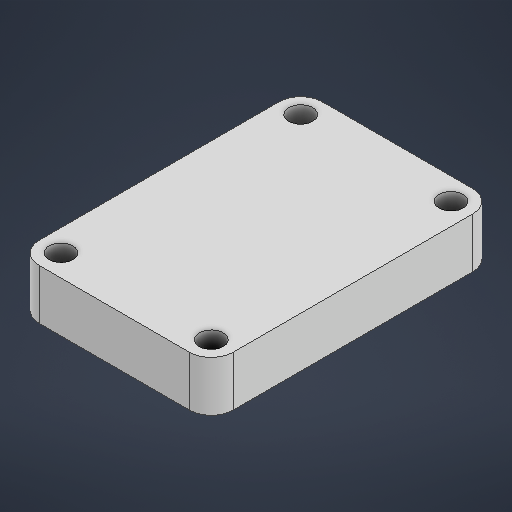
# Autodesk Inventor part: IMU
Saved by Autodesk Inventor 2026.2 (Build 302298010, 298A)
## iProperties
Created: 2026-07-16
Part Number: IMU
Material: Generic
Document SubType Name: Modeling
Designer: User
Density: 1 g/cm^3
Appearance: Default
Author: User
Autodesk Inventor part; units mm, degrees
ref_plane "YZ Plane" through (0, 0, 0) normal (1, 0, 0) x (0, 1, 0)
ref_plane "XZ Plane" through (0, 0, 0) normal (0, 1, 0) x (-1, 0, 0)
ref_plane "XY Plane" through (0, 0, 0) normal (0, 0, 1) x (1, 0, 0)
sketch "Sketch1" plane through (0, 0, 0) normal (0, 1, 0) x (-1, 0, 0)
  line L0 (0, 0) -> (17.8, 0)
  line L1 (17.8, 0) -> (17.8, -26)
  line L2 (17.8, -26) -> (0, -26)
  line L3 (0, -26) -> (0, 0)
  dimension "d0" = 17.8
  dimension "d1" = 26
  constraints: 8 end point, 2 parallel, 1 horizontal, 1 perpendicular
  measures "d0" distance of L1.end L2.end
  measures "d1" distance of L0.end L1.end
extrude "Extrusion1" add sketch "Sketch1" along normal blind 4.6
sketch "Sketch2" plane through (0, 4.6, 0) normal (0, 1, 0) x (1, 0, 0)
  line L0 (0, 0) -> (0, 26) projected
  line L1 (-17.8, 26) -> (-17.8, 0) projected
  line L2 (-17.8, 0) -> (0, 0) projected
  line L3 (0, 26) -> (-17.8, 26) projected
  line L4 (-17.8, 26) -> (-15.8, 26)
  line L5 (-15.8, 26) -> (-15.8, 24)
  line L6 (-15.8, 24) -> (-17.8, 24)
  line L7 (-17.8, 24) -> (-17.8, 26)
  line L8 (0, 26) -> (-2, 26)
  line L9 (-2, 26) -> (-2, 24)
  line L10 (-2, 24) -> (0, 24)
  line L11 (0, 24) -> (0, 26)
  line L12 (0, 0) -> (-2, 0)
  line L13 (-2, 0) -> (-2, 2)
  line L14 (-2, 2) -> (0, 2)
  line L15 (0, 2) -> (0, 0)
  line L16 (-17.8, 0) -> (-15.8, 0)
  line L17 (-15.8, 0) -> (-15.8, 2)
  line L18 (-15.8, 2) -> (-17.8, 2)
  line L19 (-17.8, 2) -> (-17.8, 0)
  dimension "d19" = 2
  dimension "d20" = 2
  dimension "d21" = 2
  dimension "d22" = 2
  dimension "d23" = 2
  dimension "d24" = 2
  dimension "d25" = 2
  dimension "d26" = 2
  constraints: 32 end point, 8 parallel, 4 coincident, 4 horizontal, 4 perpendicular
  measures "d19" distance of L5.end L6.end
  measures "d20" distance of L4.end L5.end
  measures "d21" distance of L10.end L9.end
  measures "d22" distance of L9.end L8.end
  measures "d23" distance of L13.end L14.end
  measures "d24" distance of L12.end L13.end
  measures "d25" distance of L18.end L17.end
  measures "d26" distance of L17.end L16.end
hole "Hole1" at (-15.8, 4.6, -2) at (-15.8, 4.6, -24) at (-2, 4.6, -24) at (-2, 4.6, -2) direction (0, -1, 0) diameter 2.2 end through all
fillet "Fillet1" radius 2 4 edges at (0, 2.3, -26) (0, 2.3, 0) (-17.8, 2.3, -26) (-17.8, 2.3, 0)
body "Solid1"
